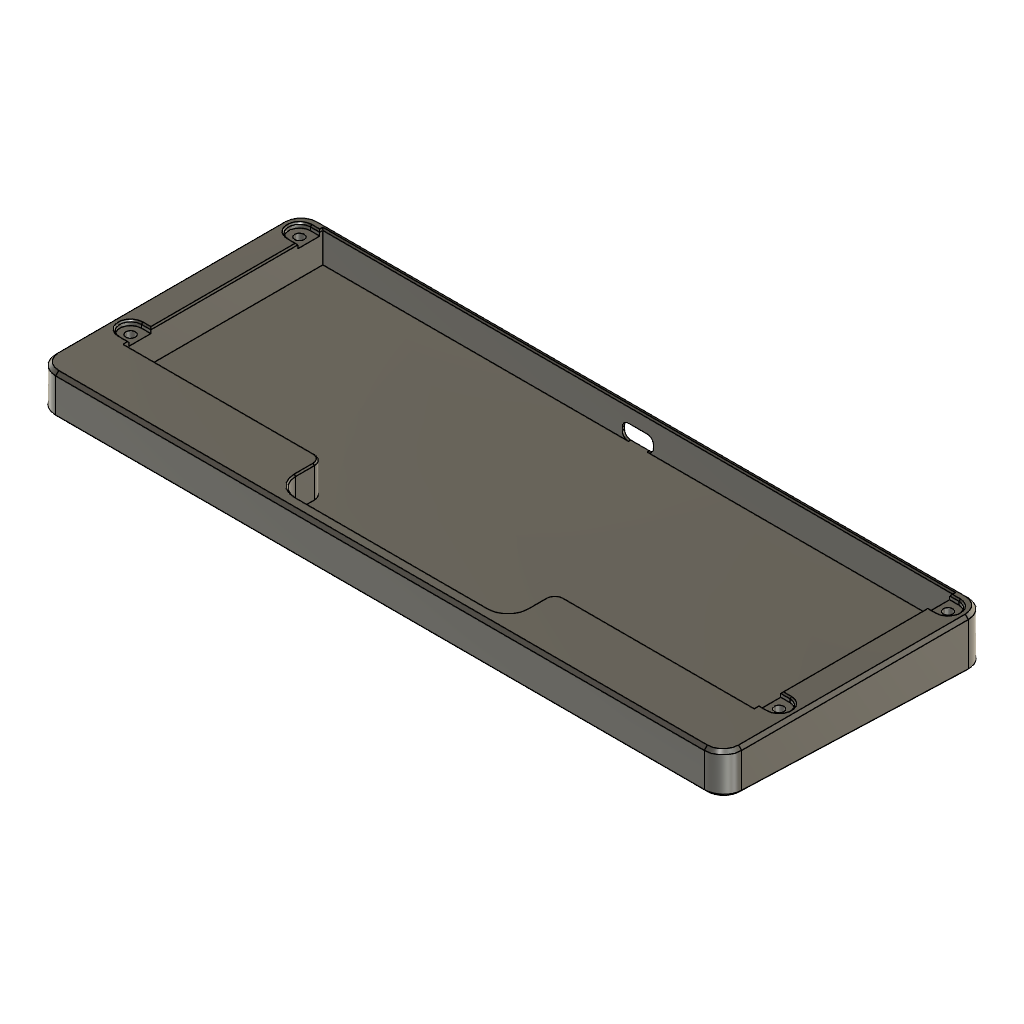
Treadstone Hull bottom (Autodesk Fusion 360 design; units mm, degrees)
Autodesk Fusion 360 part; units mm, degrees
sketch "TreadstoneHullPlate" plane through (0, 0, 0) normal (0, 0, 1) x (1, 0, 0)
  line L0 (201.025, 1.5) -> (-1, 1.5)
  line L1 (-1, 1.5) -> (-1, -62.175)
  line L2 (-1, -62.175) -> (59.9625, -62.175)
  line L3 (62.9625, -65.175) -> (62.9625, -71.2)
  arc A0 (62.9625, -71.2) -> (68.9625, -77.2) centre (68.9625, -71.2) ccw
  line L4 (68.9625, -77.2) -> (131.0625, -77.2)
  arc A1 (131.0625, -77.2) -> (137.0625, -71.2) centre (131.0625, -71.2) ccw
  line L5 (137.0625, -71.2) -> (137.0625, -65.175)
  arc A2 (140.0625, -62.175) -> (137.0625, -65.175) centre (140.0625, -65.175) ccw
  line L6 (140.0625, -62.175) -> (201.025, -62.175)
  line L7 (201.025, -62.175) -> (201.025, 1.5)
  line L8 (201.025, -60.675) -> (204.225, -60.675)
  line L9 (204.225, -53.675) -> (201.025, -53.675)
  line L10 (201.025, 0.5) -> (204.225, 0.5)
  arc A3 (204.025, -3.7) -> (204.0253, -3.7) centre (204.025, -3) ccw
  line L11 (204.0245, -3.7) -> (204.025, -3.7)
  line L12 (204.225, -6.5) -> (201.025, -6.5)
  line L13 (-4.2, -53.675) -> (-1, -53.675)
  line L14 (-1, -60.675) -> (-4.2, -60.675)
  line L15 (-1, 0.5) -> (-4.2, 0.5)
  arc A4 (-4.0003, -3.7) -> (-4, -3.7) centre (-4, -3) ccw
  line L16 (-3.9994, -3.7) -> (-4, -3.7)
  line L17 (-4.2, -6.5) -> (-1, -6.5)
  line L18 (204.225, -53.675) -> (201.025, -53.675)
  line L19 (201.025, -60.675) -> (204.225, -60.675)
  arc A5 (-4, -53.675) -> (-4, -60.675) centre (-4, -57.175) ccw
  arc A6 (-4, 0.5) -> (-4, -6.5) centre (-4, -3) ccw
  arc A7 (204.025, -6.5) -> (204.025, 0.5) centre (204.025, -3) ccw
  arc A8 (204.025, -60.675) -> (204.025, -53.675) centre (204.025, -57.175) ccw
  arc A9 (204.025, -60.675) -> (204.025, -53.675) centre (204.025, -57.175) ccw
  circle A10 centre (-4, -57.175) radius 1.5
  circle A11 centre (-4, -3) radius 1.5
  circle A12 centre (204.025, -3) radius 1.5
  circle A13 centre (204.025, -57.175) radius 1.5
  line L20 (-10, -2.5) -> (-10, -75.2)
  line L21 (210.025, -2.5) -> (210.025, -75.2)
  line L22 (100.0125, 3.5) -> (-4, 3.5)
  line L23 (100.0125, 3.5) -> (204.025, 3.5)
  line L24 (100.0125, -81.2) -> (204.025, -81.2)
  line L25 (100.0125, -81.2) -> (-4, -81.2)
  arc A14 (-4, 3.5) -> (-10, -2.5) centre (-4, -2.5) ccw
  arc A15 (-10, -75.2) -> (-4, -81.2) centre (-4, -75.2) ccw
  arc A16 (204.025, -81.2) -> (210.025, -75.2) centre (204.025, -75.2) ccw
  arc A17 (210.025, -2.5) -> (204.025, 3.5) centre (204.025, -2.5) ccw
  arc A18 (62.9625, -65.175) -> (59.9625, -62.175) centre (59.9625, -65.175) ccw
  point P0 (201.025, -61.175)
  dimension "d9" = 7
  dimension "d10" = 3
  dimension "d11" = 3
  dimension "d12" = 3
  dimension "d13" = 3
  dimension "d14" = 3
  dimension "d18" = 6
  dimension "d48" = 3
  constraint tangent L3 A0
  constraint tangent L4 A1
  constraint tangent A0 L4
  constraint tangent A1 L5
  constraint tangent L5 A2
  constraint tangent A2 L6
  constraint coincident L7 L9.end
  constraint coincident L7 L8.start
  constraint coincident L7 L12.end
  constraint coincident L7 L10.start
  constraint tangent L10 A7
  constraint tangent L9 A9
  constraint tangent L18 A8
  constraint tangent L13 A5
  constraint coincident L14 A5.end
  constraint coincident L1 L14.start
  constraint coincident L13 A5.start
  constraint concentric A4 A6
  constraint tangent L15 A6
  constraint coincident L15 A6.start
  constraint coincident L17 A6.end
  constraint coincident L10 A7.end
  constraint coincident L12 A7.start
  constraint coincident L9 A8.end
  constraint coincident L8 A8.start
  constraint coincident L1 L13.end
  constraint concentric A5 A10
  constraint concentric A4 A11
  constraint concentric A3 A12
  constraint concentric A8 A13
  constraint perpendicular L21 L24
  constraint perpendicular L20 L25
  constraint tangent L22 A14
  constraint tangent L20 A14
  constraint tangent L20 A15
  constraint tangent L25 A15
  constraint equal A14 A15
  constraint tangent L24 A16
  constraint tangent L21 A16
  constraint equal A14 A16
  constraint tangent L21 A17
  constraint tangent L23 A17
  constraint equal A14 A17
  constraint tangent L2 A18
  constraint tangent L3 A18
  measures "d9" diameter of A5
  measures "d10" distance of L1 A5.centre
  measures "d11" diameter of A10
  measures "d12" diameter of A11
  measures "d13" diameter of A12
  measures "d14" diameter of A13
  measures "d18" radius of A14
  measures "d48" radius of A18
extrude "Extrude1" add sketch "TreadstoneHullPlate" along normal blind 16 contours L20 L21 L22 L23 L24 L25 A14 A15 A16 A17
extrude "Extrude2" add sketch "TreadstoneHullPlate" along normal blind 14.5 contours L7 L10 L12 A7 | L1 L15 L17 A6 | L7 L8 L9 L18 L19 A8 A9 | L1 L13 L14 A5
extrude "Extrude3" add sketch "TreadstoneHullPlate" along normal blind 10 contours A3 | A4 | A10 | A11 | A12 | A13
extrude "Extrude4" add sketch "TreadstoneHullPlate" along normal blind 6 contours L0 L1 L2 L3 A0 L4 A1 L5 A2 L6 L7 A18
sketch "Sketch2" plane through (0, 0, 16) normal (0, 0, 1) x (-1, 0, 0)
  line L0 (1, 62.175) -> (1, 60.675)
  line L1 (1, 60.675) -> (4, 60.675)
  arc A0 (4, 53.675) -> (4, 60.675) centre (4, 57.175) ccw
  line L2 (4, 53.675) -> (1, 53.675)
  line L3 (1, 6.5) -> (4, 6.5)
  arc A1 (4, -0.5) -> (4, 6.5) centre (4, 3) ccw
  line L4 (4, -0.5) -> (1, -0.5)
  line L5 (-201.025, -1.5) -> (-201.025, -0.5)
  line L6 (-201.025, -0.5) -> (-204.025, -0.5)
  arc A2 (-204.025, 6.5) -> (-204.025, -0.5) centre (-204.025, 3) ccw
  line L7 (-204.025, 6.5) -> (-201.025, 6.5)
  line L8 (-201.025, 53.675) -> (-204.025, 53.675)
  arc A3 (-204.025, 60.675) -> (-204.025, 53.675) centre (-204.025, 57.175) ccw
  line L9 (-204.025, 60.675) -> (-201.025, 60.675)
  line L10 (4, 81.2) -> (-204.025, 81.2)
  arc A4 (-204.025, 81.2) -> (-210.025, 75.2) centre (-204.025, 75.2) ccw
  line L11 (-210.025, 75.2) -> (-210.025, 2.5)
  arc A5 (-210.025, 2.5) -> (-204.025, -3.5) centre (-204.025, 2.5) ccw
  line L12 (-204.025, -3.5) -> (4, -3.5)
  arc A6 (4, -3.5) -> (10, 2.5) centre (4, 2.5) ccw
  line L13 (10, 2.5) -> (10, 75.2)
  arc A7 (10, 75.2) -> (4, 81.2) centre (4, 75.2) ccw
  line L14 (-100.0125, -3.5) -> (-105.0125, -3.5)
  line L15 (-100.0125, -3.5) -> (-95.0125, -3.5)
  line L16 (-95.0125, -3.5) -> (-95.0125, -1)
  line L17 (-105.0125, -3.5) -> (-105.0125, -1)
  line L18 (-105.0125, -1) -> (-95.0125, -1)
  arc A8 (-62.9625, 71.2) -> (-68.9625, 77.2) centre (-68.9625, 71.2) ccw
  line L19 (-62.9625, 71.2) -> (-62.9625, 65.175)
  arc A9 (-62.9625, 65.175) -> (-59.9625, 62.175) centre (-59.9625, 65.175) ccw
  line L20 (-59.9625, 62.175) -> (1, 62.175)
  line L21 (1, 53.675) -> (1, 6.5)
  line L22 (1, -0.5) -> (1, -1.5)
  line L23 (1, -1.5) -> (-201.025, -1.5)
  line L24 (-201.025, 6.5) -> (-201.025, 53.675)
  line L25 (-201.025, 60.675) -> (-201.025, 62.175)
  line L26 (-201.025, 62.175) -> (-140.0625, 62.175)
  arc A10 (-140.0625, 62.175) -> (-137.0625, 65.175) centre (-140.0625, 65.175) ccw
  line L27 (-137.0625, 65.175) -> (-137.0625, 71.2)
  arc A11 (-131.0625, 77.2) -> (-137.0625, 71.2) centre (-131.0625, 71.2) ccw
  line L28 (-131.0625, 77.2) -> (-68.9625, 77.2)
  point P0 (-100.0125, -3.5)
  dimension "d27" = 5
  dimension "d28" = 5
  constraint coincident P0 L14.start
  constraint parallel L12 L14
  constraint parallel L12 L15
  measures "d27" distance of P0 L14.end
  measures "d28" distance of P0 L15.end
extrude "Extrude5" cut sketch "Sketch2" against normal blind 10 contours L16 L17 L18 L23 | L12 L14 L15 L16 L17 L23
extrude "Extrude6" add sketch "Sketch2" against normal blind 5 contours L16 L17 L18 L23 | L12 L14 L15 L16 L17 L23
fillet "Fillet1" radius 2 4 edges at (105.0125, 2.5, 6) (105.0125, 2.5, 11) (95.0125, 2.5, 11) (95.0125, 2.5, 6)
extrude "Extrude9" cut 1 faces at (101.6792, 1, 14.3333) along direction (0, 1, 0) blind 0.5
sketch "Sketch3" plane through (0, 3.5, 0) normal (0, 1, 0) x (-1, 0, 0)
  line L0 (-95.0125, 9) -> (-95.0125, 8)
  arc A0 (-97.0125, 6) -> (-95.0125, 8) centre (-97.0125, 8) ccw
  line L1 (-97.0125, 6) -> (-103.0125, 6)
  arc A1 (-105.0125, 8) -> (-103.0125, 6) centre (-103.0125, 8) ccw
  line L2 (-105.0125, 8) -> (-105.0125, 9)
  arc A2 (-103.0125, 11) -> (-105.0125, 9) centre (-103.0125, 9) ccw
  line L3 (-103.0125, 11) -> (-97.0125, 11)
  arc A3 (-95.0125, 9) -> (-97.0125, 11) centre (-97.0125, 9) ccw
  line L4 (4, 16) -> (-204.025, 16)
  line L5 (-204.025, 16) -> (-204.025, 0)
  line L6 (-204.025, 0) -> (4, 0)
  line L7 (4, 0) -> (4, 16)
  arc A4 (-93.0125, 9) -> (-97.0125, 13) centre (-97.0125, 9) ccw
  line L8 (-103.0125, 13) -> (-97.0125, 13)
  arc A5 (-103.0125, 13) -> (-107.0125, 9) centre (-103.0125, 9) ccw
  line L9 (-107.0125, 8) -> (-107.0125, 9)
  arc A6 (-107.0125, 8) -> (-103.0125, 4) centre (-103.0125, 8) ccw
  line L10 (-97.0125, 4) -> (-103.0125, 4)
  arc A7 (-97.0125, 4) -> (-93.0125, 8) centre (-97.0125, 8) ccw
  line L11 (-93.0125, 9) -> (-93.0125, 8)
  dimension "d35" = -2
  measures "d35" distance of A3
extrude "Extrude7" cut sketch "Sketch3" against normal blind 1.25 contours A4 L8 A5 L9 A6 L10 A7 L11
sketch "Sketch4" plane through (210.025, 0, 0) normal (1, 0, 0) x (0, 1, 0)
  line L0 (-75.2, 16) -> (-75.2, 0)
  line L1 (-75.2, 0) -> (-2.5, 0)
  line L2 (-2.5, 0) -> (-2.5, 16)
  line L3 (-81.2, 0) -> (-81.2, 16)
  line L4 (-81.2, 3.1212) -> (5, 0)
  line L5 (5, 0) -> (5.113, 3.1212)
  line L6 (5, 0) -> (10, -6)
  line L7 (10, -6) -> (-87, -6)
  line L8 (-87, -6) -> (-81.2, 3.1212)
  line L9 (-2.5, 16) -> (-75.2, 16)
  constraint coincident L3 L4.start
  constraint perpendicular L4 L5
  constraint horizontal L7
extrude "Extrude8" cut sketch "Sketch4" against normal blind 227.051 contours L0 L1 L2 L4 | L0 L1 L2 L4 L6 L7 L8
chamfer "Chamfer1" distance 1 angle 45 8 edges at (100.0125, 3.5, 16) (-8.2426, 1.7426, 16) (-10, -38.85, 16) (-8.2426, -79.4426, 16) (100.0125, -81.2, 16) (208.2676, -79.4426, 16) (210.025, -38.85, 16) (208.2676, 1.7426, 16) tangent chain off
chamfer "Chamfer2" distance 0.45 angle 45 26 edges at (100.0125, 1.5, 16) (-1, -30.0875, 16) (29.4812, -62.175, 16) (-7.5, -57.175, 16) (-2.5, -60.675, 16) (-2.5, -53.675, 16) (-7.5, -3, 16) (-2.5, -6.5, 16) (-2.5, 0.5, 16) (137.9412, -63.0537, 16) (170.5438, -62.175, 16) (62.9625, -68.1875, 16) (64.7199, -75.4426, 16) (100.0125, -77.2, 16) (135.3051, -75.4426, 16) (137.0625, -68.1875, 16) (202.525, 0.5, 16) (207.525, -3, 16) (202.525, -6.5, 16) (201.025, -30.0875, 16) (202.525, -53.675, 16) (207.525, -57.175, 16) (202.525, -60.675, 16) (201.025, -61.425, 16) (201.025, 1, 16) (-1, 1, 16) tangent chain off
chamfer "Chamfer3" distance 1 angle 45 8 edges at (94.1841, 3.5, 5.1716) (100.0125, 3.5, 4) (105.8409, 3.5, 5.1716) (107.0125, 3.5, 8.5) (105.8409, 3.5, 11.8284) (100.0125, 3.5, 13) (94.1841, 3.5, 11.8284) (93.0125, 3.5, 8.5) tangent chain off
chamfer "Chamfer4" distance 1 angle 45 1 faces at (65.3417, -52.9667, 2.0989) tangent chain off
